Autodesk Fusion 360 part; units mm, degrees
(part 7 of 7)
equation "d574 = abs(mountInset - 10 mm)"
equation "d576 = 2 * panelHeight - 2 * mountInset + 20 mm"
equation "d579 = frameZ"
equation "d581 = abs(2 * panelWidth - mountInset - 10 mm)"
equation "d582 = abs(mountInset - 10 mm)"
equation "d584 = 2 * panelHeight - 2 * mountInset + 20 mm"
equation "d587 = frameZ"
equation "d589 = abs(2 * panelWidth - mountInset - 10 mm + 7 mm)"
equation "d590 = abs(mountInset - 10 mm)"
equation "d592 = 2 * panelHeight - 2 * mountInset + 20 mm"
equation "d595 = frameZ + 1.8 mm"
equation "d597 = abs(2 * panelWidth - mountInset - 10 mm + 5 mm)"
equation "d598 = abs(mountInset - 10 mm)"
equation "d600 = 2 * panelHeight - 2 * mountInset + 20 mm"
equation "d603 = frameZ"
equation "d605 = abs(mountInset + 10 mm)"
equation "d606 = abs(mountInset - 10 mm)"
equation "d607 = panelWidth - ( mountInset ) - 20 mm"
equation "d611 = frameZ"
equation "d613 = abs(mountInset + 10 mm)"
equation "d614 = abs(mountInset - 10 mm + 7 mm)"
equation "d615 = panelWidth - ( mountInset ) - 20 mm"
equation "d619 = frameZ + 1.8 mm"
equation "d621 = abs(mountInset + 10 mm)"
equation "d622 = abs(mountInset - 10 mm + 5 mm)"
equation "d623 = panelWidth - ( mountInset ) - 20 mm"
equation "d627 = frameZ"
equation "d629 = abs(panelWidth + 10 mm)"
equation "d630 = abs(mountInset - 10 mm)"
equation "d631 = 2 * panelWidth - mountInset - ( panelWidth ) - 20 mm"
equation "d635 = frameZ"
equation "d637 = abs(panelWidth + 10 mm)"
equation "d638 = abs(mountInset - 10 mm + 7 mm)"
equation "d639 = 2 * panelWidth - mountInset - ( panelWidth ) - 20 mm"
equation "d643 = frameZ + 1.8 mm"
equation "d645 = abs(panelWidth + 10 mm)"
equation "d646 = abs(mountInset - 10 mm + 5 mm)"
equation "d647 = 2 * panelWidth - mountInset - ( panelWidth ) - 20 mm"
equation "d651 = frameZ"
equation "d653 = abs(mountInset + 10 mm)"
equation "d654 = abs(2 * panelHeight - mountInset - 10 mm)"
equation "d655 = panelWidth - ( mountInset ) - 20 mm"
equation "d659 = frameZ"
equation "d661 = abs(mountInset + 10 mm)"
equation "d662 = abs(2 * panelHeight - mountInset - 10 mm + 7 mm)"
equation "d663 = panelWidth - ( mountInset ) - 20 mm"
equation "d667 = frameZ + 1.8 mm"
equation "d669 = abs(mountInset + 10 mm)"
equation "d670 = abs(2 * panelHeight - mountInset - 10 mm + 5 mm)"
equation "d671 = panelWidth - ( mountInset ) - 20 mm"
equation "d675 = frameZ"
equation "d677 = abs(panelWidth + 10 mm)"
equation "d678 = abs(2 * panelHeight - mountInset - 10 mm)"
equation "d679 = 2 * panelWidth - mountInset - ( panelWidth ) - 20 mm"
equation "d683 = frameZ"
equation "d685 = abs(panelWidth + 10 mm)"
equation "d686 = abs(2 * panelHeight - mountInset - 10 mm + 7 mm)"
equation "d687 = 2 * panelWidth - mountInset - ( panelWidth ) - 20 mm"
equation "d691 = frameZ + 1.8 mm"
equation "d693 = abs(panelWidth + 10 mm)"
equation "d694 = abs(2 * panelHeight - mountInset - 10 mm + 5 mm)"
equation "d695 = 2 * panelWidth - mountInset - ( panelWidth ) - 20 mm"
equation "d699 = -capThickness"
equation "d701 = abs(mountInset)"
equation "d702 = abs(mountInset)"
equation "d703 = capDiameter"
equation "d704 = capThickness"
equation "d706 = -capThickness"
equation "d708 = abs(mountInset)"
equation "d709 = abs(mountInset)"
equation "d710 = screwClearance"
equation "d711 = capThickness"
equation "d713 = boardThickness"
equation "d715 = abs(mountInset)"
equation "d716 = abs(mountInset)"
equation "d717 = capDiameter"
equation "d718 = seatThickness"
equation "d720 = boardThickness"
equation "d722 = abs(mountInset)"
equation "d723 = abs(mountInset)"
equation "d724 = mountBore"
equation "d725 = seatThickness"
equation "d727 = abs(mountInset)"
equation "d728 = abs(mountInset)"
equation "d730 = boardThickness + seatThickness"
equation "d732 = boardThickness + seatThickness"
equation "d734 = abs(mountInset)"
equation "d735 = abs(mountInset)"
equation "d737 = hookClearance - seatThickness"
equation "d739 = abs(mountInset)"
equation "d740 = abs(mountInset)"
equation "d741 = screwClearance"
equation "d742 = frameZ"
equation "d744 = -capThickness - 3 mm"
equation "d746 = abs(mountInset)"
equation "d747 = abs(mountInset)"
equation "d751 = -capThickness"
equation "d753 = abs(mountInset)"
equation "d754 = abs(mountInset)"
equation "d755 = screwDiameter"
equation "d756 = frameZ + capThickness + 5 mm"
equation "d758 = frameZ + 2 mm"
equation "d760 = abs(mountInset - 4.8 mm)"
equation "d761 = abs(mountInset - 5 mm)"
equation "d766 = frameZ + 2 mm"
equation "d768 = abs(mountInset)"
equation "d769 = abs(mountInset)"
equation "d775 = -capThickness"
equation "d777 = abs(mountInset)"
equation "d778 = abs(panelHeight)"
equation "d779 = capDiameter"
equation "d780 = capThickness"
equation "d782 = -capThickness"
equation "d784 = abs(mountInset)"
equation "d785 = abs(panelHeight)"
equation "d786 = screwClearance"
equation "d787 = capThickness"
equation "d789 = boardThickness"
equation "d791 = abs(mountInset)"
equation "d792 = abs(panelHeight)"
equation "d793 = capDiameter"
equation "d794 = seatThickness"
equation "d796 = boardThickness"
equation "d798 = abs(mountInset)"
equation "d799 = abs(panelHeight)"
equation "d800 = mountBore"
equation "d801 = seatThickness"
equation "d803 = abs(mountInset)"
equation "d804 = abs(panelHeight)"
equation "d806 = boardThickness + seatThickness"
equation "d808 = boardThickness + seatThickness"
equation "d810 = abs(mountInset)"
equation "d811 = abs(panelHeight)"
equation "d813 = hookClearance - seatThickness"
equation "d815 = abs(mountInset)"
equation "d816 = abs(panelHeight)"
equation "d817 = screwClearance"
equation "d818 = frameZ"
equation "d820 = -capThickness - 3 mm"
equation "d822 = abs(mountInset)"
equation "d823 = abs(panelHeight)"
equation "d827 = -capThickness"
equation "d829 = abs(mountInset)"
equation "d830 = abs(panelHeight)"
equation "d831 = screwDiameter"
equation "d832 = frameZ + capThickness + 5 mm"
equation "d834 = frameZ + 2 mm"
equation "d836 = abs(mountInset - 4.8 mm)"
equation "d837 = abs(panelHeight - 5 mm)"
equation "d842 = frameZ + 2 mm"
equation "d844 = abs(mountInset)"
equation "d845 = abs(panelHeight)"
equation "d851 = -capThickness"
equation "d853 = abs(mountInset)"
equation "d854 = abs(2 * panelHeight - mountInset)"
equation "d855 = capDiameter"
equation "d856 = capThickness"
equation "d858 = -capThickness"
equation "d860 = abs(mountInset)"
equation "d861 = abs(2 * panelHeight - mountInset)"
equation "d862 = screwClearance"
equation "d863 = capThickness"
equation "d865 = boardThickness"
equation "d867 = abs(mountInset)"
equation "d868 = abs(2 * panelHeight - mountInset)"
equation "d869 = capDiameter"
equation "d870 = seatThickness"
equation "d872 = boardThickness"
equation "d874 = abs(mountInset)"
equation "d875 = abs(2 * panelHeight - mountInset)"
equation "d876 = mountBore"
equation "d877 = seatThickness"
equation "d879 = abs(mountInset)"
equation "d880 = abs(2 * panelHeight - mountInset)"
equation "d882 = boardThickness + seatThickness"
equation "d884 = boardThickness + seatThickness"
equation "d886 = abs(mountInset)"
equation "d887 = abs(2 * panelHeight - mountInset)"
equation "d889 = hookClearance - seatThickness"
equation "d891 = abs(mountInset)"
equation "d892 = abs(2 * panelHeight - mountInset)"
equation "d893 = screwClearance"
equation "d894 = frameZ"
equation "d896 = -capThickness - 3 mm"
equation "d898 = abs(mountInset)"
equation "d899 = abs(2 * panelHeight - mountInset)"
equation "d903 = -capThickness"
equation "d905 = abs(mountInset)"
equation "d906 = abs(2 * panelHeight - mountInset)"
equation "d907 = screwDiameter"
equation "d908 = frameZ + capThickness + 5 mm"
equation "d910 = frameZ + 2 mm"
equation "d912 = abs(mountInset - 4.8 mm)"
equation "d913 = abs(2 * panelHeight - mountInset - 5 mm)"
equation "d918 = frameZ + 2 mm"
equation "d920 = abs(mountInset)"
equation "d921 = abs(2 * panelHeight - mountInset)"
equation "d927 = -capThickness"
equation "d929 = abs(panelWidth)"
equation "d930 = abs(mountInset)"
equation "d931 = capDiameter"
equation "d932 = capThickness"
equation "d934 = -capThickness"
equation "d936 = abs(panelWidth)"
equation "d937 = abs(mountInset)"
equation "d938 = screwClearance"
equation "d939 = capThickness"
equation "d941 = boardThickness"
equation "d943 = abs(panelWidth)"
equation "d944 = abs(mountInset)"
equation "d945 = capDiameter"
equation "d946 = seatThickness"
equation "d948 = boardThickness"
equation "d950 = abs(panelWidth)"
equation "d951 = abs(mountInset)"
equation "d952 = mountBore"
equation "d953 = seatThickness"
equation "d955 = abs(panelWidth)"
equation "d956 = abs(mountInset)"
equation "d958 = boardThickness + seatThickness"
equation "d960 = boardThickness + seatThickness"
equation "d962 = abs(panelWidth)"
equation "d963 = abs(mountInset)"
equation "d965 = hookClearance - seatThickness"
equation "d967 = abs(panelWidth)"
equation "d968 = abs(mountInset)"
equation "d969 = screwClearance"
equation "d970 = frameZ"
equation "d972 = -capThickness - 3 mm"
equation "d974 = abs(panelWidth)"
equation "d975 = abs(mountInset)"
equation "d979 = -capThickness"
equation "d981 = abs(panelWidth)"
equation "d982 = abs(mountInset)"
equation "d983 = screwDiameter"
equation "d984 = frameZ + capThickness + 5 mm"
equation "d986 = frameZ + 2 mm"
equation "d988 = abs(panelWidth - 4.8 mm)"
equation "d989 = abs(mountInset - 5 mm)"
equation "d994 = frameZ + 2 mm"
equation "d996 = abs(panelWidth)"
equation "d997 = abs(mountInset)"
equation "d1003 = -capThickness"
equation "d1005 = abs(panelWidth)"
equation "d1006 = abs(panelHeight)"
equation "d1007 = capDiameter"
equation "d1008 = capThickness"
equation "d1010 = -capThickness"
equation "d1012 = abs(panelWidth)"
equation "d1013 = abs(panelHeight)"
equation "d1014 = screwClearance"
equation "d1015 = capThickness"
equation "d1017 = boardThickness"
equation "d1019 = abs(panelWidth)"
equation "d1020 = abs(panelHeight)"
equation "d1021 = capDiameter"
equation "d1022 = seatThickness"
equation "d1024 = boardThickness"
equation "d1026 = abs(panelWidth)"
equation "d1027 = abs(panelHeight)"
equation "d1028 = mountBore"
equation "d1029 = seatThickness"
equation "d1031 = abs(panelWidth)"
equation "d1032 = abs(panelHeight)"
equation "d1034 = boardThickness + seatThickness"
equation "d1036 = boardThickness + seatThickness"
equation "d1038 = abs(panelWidth)"
equation "d1039 = abs(panelHeight)"
equation "d1041 = hookClearance - seatThickness"
equation "d1043 = abs(panelWidth)"
equation "d1044 = abs(panelHeight)"
equation "d1045 = screwClearance"
equation "d1046 = frameZ"
equation "d1048 = -capThickness - 3 mm"
equation "d1050 = abs(panelWidth)"
equation "d1051 = abs(panelHeight)"
equation "d1055 = -capThickness"
equation "d1057 = abs(panelWidth)"
equation "d1058 = abs(panelHeight)"
equation "d1059 = screwDiameter"
equation "d1060 = frameZ + capThickness + 5 mm"
equation "d1062 = frameZ + 2 mm"
equation "d1064 = abs(panelWidth - 4.8 mm)"
equation "d1065 = abs(panelHeight - 5 mm)"
equation "d1070 = frameZ + 2 mm"
equation "d1072 = abs(panelWidth)"
equation "d1073 = abs(panelHeight)"
equation "d1079 = -capThickness"
equation "d1081 = abs(panelWidth)"
equation "d1082 = abs(2 * panelHeight - mountInset)"
equation "d1083 = capDiameter"
equation "d1084 = capThickness"
equation "d1086 = -capThickness"
equation "d1088 = abs(panelWidth)"
equation "d1089 = abs(2 * panelHeight - mountInset)"
equation "d1090 = screwClearance"
equation "d1091 = capThickness"
equation "d1093 = boardThickness"
equation "d1095 = abs(panelWidth)"
equation "d1096 = abs(2 * panelHeight - mountInset)"
equation "d1097 = capDiameter"
equation "d1098 = seatThickness"
equation "d1100 = boardThickness"
equation "d1102 = abs(panelWidth)"
equation "d1103 = abs(2 * panelHeight - mountInset)"
equation "d1104 = mountBore"
equation "d1105 = seatThickness"
equation "d1107 = abs(panelWidth)"
equation "d1108 = abs(2 * panelHeight - mountInset)"
equation "d1110 = boardThickness + seatThickness"
equation "d1112 = boardThickness + seatThickness"
equation "d1114 = abs(panelWidth)"
equation "d1115 = abs(2 * panelHeight - mountInset)"
equation "d1117 = hookClearance - seatThickness"
equation "d1119 = abs(panelWidth)"
equation "d1120 = abs(2 * panelHeight - mountInset)"
equation "d1121 = screwClearance"
equation "d1122 = frameZ"
equation "d1124 = -capThickness - 3 mm"
equation "d1126 = abs(panelWidth)"
equation "d1127 = abs(2 * panelHeight - mountInset)"
equation "d1131 = -capThickness"
equation "d1133 = abs(panelWidth)"
equation "d1134 = abs(2 * panelHeight - mountInset)"
equation "d1135 = screwDiameter"
equation "d1136 = frameZ + capThickness + 5 mm"
equation "d1138 = frameZ + 2 mm"
equation "d1140 = abs(panelWidth - 4.8 mm)"
equation "d1141 = abs(2 * panelHeight - mountInset - 5 mm)"
equation "d1146 = frameZ + 2 mm"
equation "d1148 = abs(panelWidth)"
equation "d1149 = abs(2 * panelHeight - mountInset)"
equation "d1155 = -capThickness"
equation "d1157 = abs(2 * panelWidth - mountInset)"
equation "d1158 = abs(mountInset)"
equation "d1159 = capDiameter"
equation "d1160 = capThickness"
equation "d1162 = -capThickness"
equation "d1164 = abs(2 * panelWidth - mountInset)"
equation "d1165 = abs(mountInset)"
equation "d1166 = screwClearance"
equation "d1167 = capThickness"
equation "d1169 = boardThickness"
equation "d1171 = abs(2 * panelWidth - mountInset)"
equation "d1172 = abs(mountInset)"
equation "d1173 = capDiameter"
equation "d1174 = seatThickness"
equation "d1176 = boardThickness"
equation "d1178 = abs(2 * panelWidth - mountInset)"
equation "d1179 = abs(mountInset)"
equation "d1180 = mountBore"
equation "d1181 = seatThickness"
equation "d1183 = abs(2 * panelWidth - mountInset)"
equation "d1184 = abs(mountInset)"
equation "d1186 = boardThickness + seatThickness"
equation "d1188 = boardThickness + seatThickness"
equation "d1190 = abs(2 * panelWidth - mountInset)"
equation "d1191 = abs(mountInset)"
equation "d1193 = hookClearance - seatThickness"
equation "d1195 = abs(2 * panelWidth - mountInset)"
equation "d1196 = abs(mountInset)"
equation "d1197 = screwClearance"
equation "d1198 = frameZ"
equation "d1200 = -capThickness - 3 mm"
equation "d1202 = abs(2 * panelWidth - mountInset)"
equation "d1203 = abs(mountInset)"
equation "d1207 = -capThickness"
equation "d1209 = abs(2 * panelWidth - mountInset)"
equation "d1210 = abs(mountInset)"
equation "d1211 = screwDiameter"
equation "d1212 = frameZ + capThickness + 5 mm"
equation "d1214 = frameZ + 2 mm"
equation "d1216 = abs(2 * panelWidth - mountInset - 4.8 mm)"
equation "d1217 = abs(mountInset - 5 mm)"
equation "d1222 = frameZ + 2 mm"
equation "d1224 = abs(2 * panelWidth - mountInset)"
equation "d1225 = abs(mountInset)"
equation "d1231 = -capThickness"
equation "d1233 = abs(2 * panelWidth - mountInset)"
equation "d1234 = abs(panelHeight)"
equation "d1235 = capDiameter"
equation "d1236 = capThickness"
equation "d1238 = -capThickness"
equation "d1240 = abs(2 * panelWidth - mountInset)"
equation "d1241 = abs(panelHeight)"
equation "d1242 = screwClearance"
equation "d1243 = capThickness"
equation "d1245 = boardThickness"
equation "d1247 = abs(2 * panelWidth - mountInset)"
equation "d1248 = abs(panelHeight)"
equation "d1249 = capDiameter"
equation "d1250 = seatThickness"
equation "d1252 = boardThickness"
equation "d1254 = abs(2 * panelWidth - mountInset)"
equation "d1255 = abs(panelHeight)"
equation "d1256 = mountBore"
equation "d1257 = seatThickness"
equation "d1259 = abs(2 * panelWidth - mountInset)"
equation "d1260 = abs(panelHeight)"
equation "d1262 = boardThickness + seatThickness"
equation "d1264 = boardThickness + seatThickness"
equation "d1266 = abs(2 * panelWidth - mountInset)"
equation "d1267 = abs(panelHeight)"
equation "d1269 = hookClearance - seatThickness"
equation "d1271 = abs(2 * panelWidth - mountInset)"
equation "d1272 = abs(panelHeight)"
equation "d1273 = screwClearance"
equation "d1274 = frameZ"
equation "d1276 = -capThickness - 3 mm"
equation "d1278 = abs(2 * panelWidth - mountInset)"
equation "d1279 = abs(panelHeight)"
equation "d1283 = -capThickness"
equation "d1285 = abs(2 * panelWidth - mountInset)"
equation "d1286 = abs(panelHeight)"
equation "d1287 = screwDiameter"
equation "d1288 = frameZ + capThickness + 5 mm"
equation "d1290 = frameZ + 2 mm"
equation "d1292 = abs(2 * panelWidth - mountInset - 4.8 mm)"
equation "d1293 = abs(panelHeight - 5 mm)"
equation "d1298 = frameZ + 2 mm"
equation "d1300 = abs(2 * panelWidth - mountInset)"
equation "d1301 = abs(panelHeight)"
equation "d1307 = -capThickness"
equation "d1309 = abs(2 * panelWidth - mountInset)"
equation "d1310 = abs(2 * panelHeight - mountInset)"
equation "d1311 = capDiameter"
equation "d1312 = capThickness"
equation "d1314 = -capThickness"
equation "d1316 = abs(2 * panelWidth - mountInset)"
equation "d1317 = abs(2 * panelHeight - mountInset)"
equation "d1318 = screwClearance"
equation "d1319 = capThickness"
equation "d1321 = boardThickness"
equation "d1323 = abs(2 * panelWidth - mountInset)"
equation "d1324 = abs(2 * panelHeight - mountInset)"
equation "d1325 = capDiameter"
equation "d1326 = seatThickness"
equation "d1328 = boardThickness"
equation "d1330 = abs(2 * panelWidth - mountInset)"
equation "d1331 = abs(2 * panelHeight - mountInset)"
equation "d1332 = mountBore"
equation "d1333 = seatThickness"
equation "d1335 = abs(2 * panelWidth - mountInset)"
equation "d1336 = abs(2 * panelHeight - mountInset)"
equation "d1338 = boardThickness + seatThickness"
equation "d1340 = boardThickness + seatThickness"
equation "d1342 = abs(2 * panelWidth - mountInset)"
equation "d1343 = abs(2 * panelHeight - mountInset)"
equation "d1345 = hookClearance - seatThickness"
equation "d1347 = abs(2 * panelWidth - mountInset)"
equation "d1348 = abs(2 * panelHeight - mountInset)"
equation "d1349 = screwClearance"
equation "d1350 = frameZ"
equation "d1352 = -capThickness - 3 mm"
equation "d1354 = abs(2 * panelWidth - mountInset)"
equation "d1355 = abs(2 * panelHeight - mountInset)"
equation "d1359 = -capThickness"
equation "d1361 = abs(2 * panelWidth - mountInset)"
equation "d1362 = abs(2 * panelHeight - mountInset)"
equation "d1363 = screwDiameter"
equation "d1364 = frameZ + capThickness + 5 mm"
equation "d1366 = frameZ + 2 mm"
equation "d1368 = abs(2 * panelWidth - mountInset - 4.8 mm)"
equation "d1369 = abs(2 * panelHeight - mountInset - 5 mm)"
equation "d1374 = frameZ + 2 mm"
equation "d1376 = abs(2 * panelWidth - mountInset)"
equation "d1377 = abs(2 * panelHeight - mountInset)"
equation "d1383 = frameZ + 20 mm"
equation "d1385 = abs(mountInset - 3 mm)"
equation "d1386 = abs(mountInset - 10 mm)"
equation "d1388 = 2 * panelHeight - 2 * mountInset + 20 mm"
equation "d1391 = frameZ + 18.2 mm"
equation "d1393 = abs(mountInset - 5 mm)"
equation "d1394 = abs(mountInset - 10 mm)"
equation "d1396 = 2 * panelHeight - 2 * mountInset + 20 mm"
equation "d1399 = frameZ + 20 mm"
equation "d1401 = abs(panelWidth - 3 mm)"
equation "d1402 = abs(mountInset - 10 mm)"
equation "d1404 = 2 * panelHeight - 2 * mountInset + 20 mm"
equation "d1407 = frameZ + 18.2 mm"
equation "d1409 = abs(panelWidth - 5 mm)"
equation "d1410 = abs(mountInset - 10 mm)"
equation "d1412 = 2 * panelHeight - 2 * mountInset + 20 mm"
equation "d1415 = frameZ + 20 mm"
equation "d1417 = abs(2 * panelWidth - mountInset - 3 mm)"
equation "d1418 = abs(mountInset - 10 mm)"
equation "d1420 = 2 * panelHeight - 2 * mountInset + 20 mm"
equation "d1423 = frameZ + 18.2 mm"
equation "d1425 = abs(2 * panelWidth - mountInset - 5 mm)"
equation "d1426 = abs(mountInset - 10 mm)"
equation "d1428 = 2 * panelHeight - 2 * mountInset + 20 mm"
equation "d1431 = frameZ + 20 mm"
equation "d1433 = abs(mountInset + 10 mm)"
equation "d1434 = abs(mountInset - 3 mm)"
equation "d1435 = panelWidth - ( mountInset ) - 20 mm"
equation "d1439 = frameZ + 18.2 mm"
equation "d1441 = abs(mountInset + 10 mm)"
equation "d1442 = abs(mountInset - 5 mm)"
equation "d1443 = panelWidth - ( mountInset ) - 20 mm"
equation "d1447 = frameZ + 20 mm"
equation "d1449 = abs(panelWidth + 10 mm)"
equation "d1450 = abs(mountInset - 3 mm)"
equation "d1451 = 2 * panelWidth - mountInset - ( panelWidth ) - 20 mm"
equation "d1455 = frameZ + 18.2 mm"
equation "d1457 = abs(panelWidth + 10 mm)"
equation "d1458 = abs(mountInset - 5 mm)"
equation "d1459 = 2 * panelWidth - mountInset - ( panelWidth ) - 20 mm"
equation "d1463 = frameZ + 20 mm"
equation "d1465 = abs(mountInset + ( -8 mm ))"
equation "d1466 = abs(mountInset - 8 mm)"
equation "d1471 = frameZ + 20 mm"
equation "d1473 = abs(mountInset + ( 0 mm ))"
equation "d1474 = abs(mountInset)"
equation "d1478 = frameZ + 23 mm"
equation "d1480 = abs(mountInset + ( 0 mm ))"
equation "d1481 = abs(mountInset)"
equation "d1485 = frameZ + 23 mm"
equation "d1487 = abs(mountInset + ( 0 mm ))"
equation "d1488 = abs(mountInset)"
equation "d1492 = frameZ + 14 mm"
equation "d1494 = abs(mountInset + ( 0 mm ) - 4.8 mm)"
equation "d1495 = abs(mountInset - 4.8 mm)"
equation "d1500 = frameZ + 14 mm"
equation "d1502 = abs(mountInset + ( 0 mm ))"
equation "d1503 = abs(mountInset)"
equation "d1509 = frameZ + 20 mm"
equation "d1511 = abs(mountInset + ( 20 mm ))"
equation "d1512 = abs(mountInset)"
equation "d1516 = frameZ + 23 mm"
equation "d1518 = abs(mountInset + ( 20 mm ))"
equation "d1519 = abs(mountInset)"
equation "d1523 = frameZ + 23 mm"
equation "d1525 = abs(mountInset + ( 20 mm ))"
equation "d1526 = abs(mountInset)"
equation "d1530 = frameZ + 14 mm"
equation "d1532 = abs(mountInset + ( 20 mm ) - 4.8 mm)"
equation "d1533 = abs(mountInset - 4.8 mm)"
equation "d1538 = frameZ + 14 mm"
equation "d1540 = abs(mountInset + ( 20 mm ))"
equation "d1541 = abs(mountInset)"
equation "d1547 = frameZ + 20 mm"
equation "d1549 = abs(panelWidth + ( -28 mm ))"
equation "d1550 = abs(mountInset - 8 mm)"
equation "d1555 = frameZ + 20 mm"
equation "d1557 = abs(panelWidth + ( -20 mm ))"
equation "d1558 = abs(mountInset)"
equation "d1562 = frameZ + 23 mm"
equation "d1564 = abs(panelWidth + ( -20 mm ))"
equation "d1565 = abs(mountInset)"
equation "d1569 = frameZ + 23 mm"
equation "d1571 = abs(panelWidth + ( -20 mm ))"
equation "d1572 = abs(mountInset)"
equation "d1576 = frameZ + 14 mm"
equation "d1578 = abs(panelWidth + ( -20 mm ) - 4.8 mm)"
equation "d1579 = abs(mountInset - 4.8 mm)"
equation "d1584 = frameZ + 14 mm"
equation "d1586 = abs(panelWidth + ( -20 mm ))"
equation "d1587 = abs(mountInset)"
equation "d1593 = frameZ + 20 mm"
equation "d1595 = abs(panelWidth + ( 0 mm ))"
equation "d1596 = abs(mountInset)"
equation "d1600 = frameZ + 23 mm"
equation "d1602 = abs(panelWidth + ( 0 mm ))"
equation "d1603 = abs(mountInset)"
equation "d1607 = frameZ + 23 mm"
equation "d1609 = abs(panelWidth + ( 0 mm ))"
equation "d1610 = abs(mountInset)"
equation "d1614 = frameZ + 14 mm"
equation "d1616 = abs(panelWidth + ( 0 mm ) - 4.8 mm)"
equation "d1617 = abs(mountInset - 4.8 mm)"
equation "d1622 = frameZ + 14 mm"
equation "d1624 = abs(panelWidth + ( 0 mm ))"
equation "d1625 = abs(mountInset)"
equation "d1631 = frameZ + 20 mm"
equation "d1633 = abs(panelWidth + ( 20 mm ))"
equation "d1634 = abs(mountInset)"
equation "d1638 = frameZ + 23 mm"
equation "d1640 = abs(panelWidth + ( 20 mm ))"
equation "d1641 = abs(mountInset)"
equation "d1645 = frameZ + 23 mm"
equation "d1647 = abs(panelWidth + ( 20 mm ))"
equation "d1648 = abs(mountInset)"
equation "d1652 = frameZ + 14 mm"
equation "d1654 = abs(panelWidth + ( 20 mm ) - 4.8 mm)"
equation "d1655 = abs(mountInset - 4.8 mm)"
equation "d1660 = frameZ + 14 mm"
equation "d1662 = abs(panelWidth + ( 20 mm ))"
equation "d1663 = abs(mountInset)"
equation "d1669 = frameZ + 20 mm"
equation "d1671 = abs(2 * panelWidth - mountInset + ( -28 mm ))"
equation "d1672 = abs(mountInset - 8 mm)"
equation "d1677 = frameZ + 20 mm"
equation "d1679 = abs(2 * panelWidth - mountInset + ( -20 mm ))"
equation "d1680 = abs(mountInset)"
equation "d1684 = frameZ + 23 mm"
equation "d1686 = abs(2 * panelWidth - mountInset + ( -20 mm ))"
equation "d1687 = abs(mountInset)"
equation "d1691 = frameZ + 23 mm"
equation "d1693 = abs(2 * panelWidth - mountInset + ( -20 mm ))"
equation "d1694 = abs(mountInset)"
equation "d1698 = frameZ + 14 mm"
equation "d1700 = abs(2 * panelWidth - mountInset + ( -20 mm ) - 4.8 mm)"
equation "d1701 = abs(mountInset - 4.8 mm)"
equation "d1706 = frameZ + 14 mm"
equation "d1708 = abs(2 * panelWidth - mountInset + ( -20 mm ))"
equation "d1709 = abs(mountInset)"
equation "d1715 = frameZ + 20 mm"
equation "d1717 = abs(2 * panelWidth - mountInset + ( 0 mm ))"
equation "d1718 = abs(mountInset)"
equation "d1722 = frameZ + 23 mm"
equation "d1724 = abs(2 * panelWidth - mountInset + ( 0 mm ))"
equation "d1725 = abs(mountInset)"
equation "d1729 = frameZ + 23 mm"
equation "d1731 = abs(2 * panelWidth - mountInset + ( 0 mm ))"
equation "d1732 = abs(mountInset)"
equation "d1736 = frameZ + 14 mm"
equation "d1738 = abs(2 * panelWidth - mountInset + ( 0 mm ) - 4.8 mm)"
equation "d1739 = abs(mountInset - 4.8 mm)"
equation "d1744 = frameZ + 14 mm"
equation "d1746 = abs(2 * panelWidth - mountInset + ( 0 mm ))"
equation "d1747 = abs(mountInset)"
equation "d1753 = frameZ + 20 mm"
equation "d1755 = abs(mountInset + 10 mm)"
equation "d1756 = abs(2 * panelHeight - mountInset - 3 mm)"
equation "d1757 = panelWidth - ( mountInset ) - 20 mm"
equation "d1761 = frameZ + 18.2 mm"
equation "d1763 = abs(mountInset + 10 mm)"
equation "d1764 = abs(2 * panelHeight - mountInset - 5 mm)"
equation "d1765 = panelWidth - ( mountInset ) - 20 mm"
equation "d1769 = frameZ + 20 mm"
equation "d1771 = abs(panelWidth + 10 mm)"
equation "d1772 = abs(2 * panelHeight - mountInset - 3 mm)"
equation "d1773 = 2 * panelWidth - mountInset - ( panelWidth ) - 20 mm"
equation "d1777 = frameZ + 18.2 mm"
equation "d1779 = abs(panelWidth + 10 mm)"
equation "d1780 = abs(2 * panelHeight - mountInset - 5 mm)"
equation "d1781 = 2 * panelWidth - mountInset - ( panelWidth ) - 20 mm"
equation "d1785 = frameZ + 20 mm"
equation "d1787 = abs(mountInset + ( -8 mm ))"
equation "d1788 = abs(2 * panelHeight - mountInset - 8 mm)"
equation "d1793 = frameZ + 20 mm"
equation "d1795 = abs(mountInset + ( 0 mm ))"
equation "d1796 = abs(2 * panelHeight - mountInset)"
equation "d1800 = frameZ + 23 mm"
equation "d1802 = abs(mountInset + ( 0 mm ))"
equation "d1803 = abs(2 * panelHeight - mountInset)"
equation "d1807 = frameZ + 23 mm"
equation "d1809 = abs(mountInset + ( 0 mm ))"
equation "d1810 = abs(2 * panelHeight - mountInset)"
equation "d1814 = frameZ + 14 mm"
equation "d1816 = abs(mountInset + ( 0 mm ) - 4.8 mm)"
equation "d1817 = abs(2 * panelHeight - mountInset - 4.8 mm)"
equation "d1822 = frameZ + 14 mm"
equation "d1824 = abs(mountInset + ( 0 mm ))"
equation "d1825 = abs(2 * panelHeight - mountInset)"
equation "d1831 = frameZ + 20 mm"
equation "d1833 = abs(mountInset + ( 20 mm ))"
equation "d1834 = abs(2 * panelHeight - mountInset)"
equation "d1838 = frameZ + 23 mm"
equation "d1840 = abs(mountInset + ( 20 mm ))"
equation "d1841 = abs(2 * panelHeight - mountInset)"
equation "d1845 = frameZ + 23 mm"
equation "d1847 = abs(mountInset + ( 20 mm ))"
equation "d1848 = abs(2 * panelHeight - mountInset)"
equation "d1852 = frameZ + 14 mm"
equation "d1854 = abs(mountInset + ( 20 mm ) - 4.8 mm)"
equation "d1855 = abs(2 * panelHeight - mountInset - 4.8 mm)"
equation "d1860 = frameZ + 14 mm"
equation "d1862 = abs(mountInset + ( 20 mm ))"
equation "d1863 = abs(2 * panelHeight - mountInset)"
equation "d1869 = frameZ + 20 mm"
equation "d1871 = abs(panelWidth + ( -28 mm ))"
equation "d1872 = abs(2 * panelHeight - mountInset - 8 mm)"
equation "d1877 = frameZ + 20 mm"
equation "d1879 = abs(panelWidth + ( -20 mm ))"
equation "d1880 = abs(2 * panelHeight - mountInset)"
equation "d1884 = frameZ + 23 mm"
equation "d1886 = abs(panelWidth + ( -20 mm ))"
equation "d1887 = abs(2 * panelHeight - mountInset)"
equation "d1891 = frameZ + 23 mm"
equation "d1893 = abs(panelWidth + ( -20 mm ))"
equation "d1894 = abs(2 * panelHeight - mountInset)"
equation "d1898 = frameZ + 14 mm"
equation "d1900 = abs(panelWidth + ( -20 mm ) - 4.8 mm)"
equation "d1901 = abs(2 * panelHeight - mountInset - 4.8 mm)"
equation "d1906 = frameZ + 14 mm"
equation "d1908 = abs(panelWidth + ( -20 mm ))"
equation "d1909 = abs(2 * panelHeight - mountInset)"
equation "d1915 = frameZ + 20 mm"
equation "d1917 = abs(panelWidth + ( 0 mm ))"
equation "d1918 = abs(2 * panelHeight - mountInset)"
equation "d1922 = frameZ + 23 mm"
equation "d1924 = abs(panelWidth + ( 0 mm ))"
equation "d1925 = abs(2 * panelHeight - mountInset)"
equation "d1929 = frameZ + 23 mm"
equation "d1931 = abs(panelWidth + ( 0 mm ))"
equation "d1932 = abs(2 * panelHeight - mountInset)"
equation "d1936 = frameZ + 14 mm"
equation "d1938 = abs(panelWidth + ( 0 mm ) - 4.8 mm)"
equation "d1939 = abs(2 * panelHeight - mountInset - 4.8 mm)"
equation "d1944 = frameZ + 14 mm"
equation "d1946 = abs(panelWidth + ( 0 mm ))"
equation "d1947 = abs(2 * panelHeight - mountInset)"
equation "d1953 = frameZ + 20 mm"
equation "d1955 = abs(panelWidth + ( 20 mm ))"
equation "d1956 = abs(2 * panelHeight - mountInset)"
equation "d1960 = frameZ + 23 mm"
equation "d1962 = abs(panelWidth + ( 20 mm ))"
equation "d1963 = abs(2 * panelHeight - mountInset)"
equation "d1967 = frameZ + 23 mm"
equation "d1969 = abs(panelWidth + ( 20 mm ))"
equation "d1970 = abs(2 * panelHeight - mountInset)"
equation "d1974 = frameZ + 14 mm"
equation "d1976 = abs(panelWidth + ( 20 mm ) - 4.8 mm)"
equation "d1977 = abs(2 * panelHeight - mountInset - 4.8 mm)"
equation "d1982 = frameZ + 14 mm"
equation "d1984 = abs(panelWidth + ( 20 mm ))"
equation "d1985 = abs(2 * panelHeight - mountInset)"
equation "d1991 = frameZ + 20 mm"
equation "d1993 = abs(2 * panelWidth - mountInset + ( -28 mm ))"
equation "d1994 = abs(2 * panelHeight - mountInset - 8 mm)"
equation "d1999 = frameZ + 20 mm"
equation "d2001 = abs(2 * panelWidth - mountInset + ( -20 mm ))"
equation "d2002 = abs(2 * panelHeight - mountInset)"
equation "d2006 = frameZ + 23 mm"
equation "d2008 = abs(2 * panelWidth - mountInset + ( -20 mm ))"
equation "d2009 = abs(2 * panelHeight - mountInset)"
equation "d2013 = frameZ + 23 mm"
equation "d2015 = abs(2 * panelWidth - mountInset + ( -20 mm ))"
equation "d2016 = abs(2 * panelHeight - mountInset)"
equation "d2020 = frameZ + 14 mm"
equation "d2022 = abs(2 * panelWidth - mountInset + ( -20 mm ) - 4.8 mm)"
equation "d2023 = abs(2 * panelHeight - mountInset - 4.8 mm)"
equation "d2028 = frameZ + 14 mm"
equation "d2030 = abs(2 * panelWidth - mountInset + ( -20 mm ))"
equation "d2031 = abs(2 * panelHeight - mountInset)"
equation "d2037 = frameZ + 20 mm"
equation "d2039 = abs(2 * panelWidth - mountInset + ( 0 mm ))"
equation "d2040 = abs(2 * panelHeight - mountInset)"
equation "d2044 = frameZ + 23 mm"
equation "d2046 = abs(2 * panelWidth - mountInset + ( 0 mm ))"
equation "d2047 = abs(2 * panelHeight - mountInset)"
equation "d2051 = frameZ + 23 mm"
equation "d2053 = abs(2 * panelWidth - mountInset + ( 0 mm ))"
equation "d2054 = abs(2 * panelHeight - mountInset)"
equation "d2058 = frameZ + 14 mm"
equation "d2060 = abs(2 * panelWidth - mountInset + ( 0 mm ) - 4.8 mm)"
equation "d2061 = abs(2 * panelHeight - mountInset - 4.8 mm)"
equation "d2066 = frameZ + 14 mm"
equation "d2068 = abs(2 * panelWidth - mountInset + ( 0 mm ))"
equation "d2069 = abs(2 * panelHeight - mountInset)"
equation "wallGap = 10 mm" comment "Frame rear to wall plane; metal bracket clearance, site-specific"
equation "wallAnchorClearance = 6.5 mm" comment "Placeholder anchor shank clearance; select for actual wall"
equation "d2077 = frameZ + 20 mm"
equation "d2079 = abs(mountInset - 10 mm)"
equation "d2080 = abs(panelHeight / 2 - 15 mm)"
equation "d2085 = frameZ + 23 mm"
equation "d2087 = abs(mountInset + 7 mm)"
equation "d2088 = abs(panelHeight / 2 - 15 mm)"
equation "d2091 = wallGap - 6 mm"
equation "d2093 = frameZ + 20 mm + wallGap - 3 mm"
equation "d2095 = abs(mountInset + 7 mm)"
equation "d2096 = abs(panelHeight / 2 - 15 mm)"
equation "d2101 = frameZ + 20 mm + wallGap - 3 mm"
equation "d2103 = abs(mountInset + 22 mm)"
equation "d2104 = abs(panelHeight / 2)"
equation "d2105 = wallAnchorClearance"
equation "d2108 = frameZ + 20 mm"
equation "d2110 = abs(mountInset)"
equation "d2111 = abs(panelHeight / 2 - 8 mm)"
equation "d2115 = frameZ + 23 mm"
equation "d2117 = abs(mountInset)"
equation "d2118 = abs(panelHeight / 2 - 8 mm)"
equation "d2122 = frameZ + 23 mm"
equation "d2124 = abs(mountInset)"
equation "d2125 = abs(panelHeight / 2 - 8 mm)"
equation "d2129 = frameZ + 14 mm"
equation "d2131 = abs(mountInset - 4.8 mm)"
equation "d2132 = abs(panelHeight / 2 - 8 mm - 4.8 mm)"
equation "d2137 = frameZ + 14 mm"
equation "d2139 = abs(mountInset)"
equation "d2140 = abs(panelHeight / 2 - 8 mm)"
equation "d2146 = frameZ + 20 mm"
equation "d2148 = abs(mountInset)"
equation "d2149 = abs(panelHeight / 2 + 8 mm)"
equation "d2153 = frameZ + 23 mm"
equation "d2155 = abs(mountInset)"
equation "d2156 = abs(panelHeight / 2 + 8 mm)"
equation "d2160 = frameZ + 23 mm"
equation "d2162 = abs(mountInset)"
equation "d2163 = abs(panelHeight / 2 + 8 mm)"
equation "d2167 = frameZ + 14 mm"
equation "d2169 = abs(mountInset - 4.8 mm)"
equation "d2170 = abs(panelHeight / 2 + 8 mm - 4.8 mm)"
equation "d2175 = frameZ + 14 mm"
equation "d2177 = abs(mountInset)"
equation "d2178 = abs(panelHeight / 2 + 8 mm)"
equation "d2184 = frameZ + 20 mm"
equation "d2186 = abs(mountInset - 10 mm)"
equation "d2187 = abs(3 * panelHeight / 2 - 15 mm)"
equation "d2192 = frameZ + 23 mm"
equation "d2194 = abs(mountInset + 7 mm)"
equation "d2195 = abs(3 * panelHeight / 2 - 15 mm)"
equation "d2198 = wallGap - 6 mm"
equation "d2200 = frameZ + 20 mm + wallGap - 3 mm"
equation "d2202 = abs(mountInset + 7 mm)"
equation "d2203 = abs(3 * panelHeight / 2 - 15 mm)"
equation "d2208 = frameZ + 20 mm + wallGap - 3 mm"
equation "d2210 = abs(mountInset + 22 mm)"
equation "d2211 = abs(3 * panelHeight / 2)"
equation "d2212 = wallAnchorClearance"
equation "d2215 = frameZ + 20 mm"
equation "d2217 = abs(mountInset)"
equation "d2218 = abs(3 * panelHeight / 2 - 8 mm)"
equation "d2222 = frameZ + 23 mm"
equation "d2224 = abs(mountInset)"
equation "d2225 = abs(3 * panelHeight / 2 - 8 mm)"
equation "d2229 = frameZ + 23 mm"
equation "d2231 = abs(mountInset)"
equation "d2232 = abs(3 * panelHeight / 2 - 8 mm)"
equation "d2236 = frameZ + 14 mm"
equation "d2238 = abs(mountInset - 4.8 mm)"
equation "d2239 = abs(3 * panelHeight / 2 - 8 mm - 4.8 mm)"
equation "d2244 = frameZ + 14 mm"
equation "d2246 = abs(mountInset)"
equation "d2247 = abs(3 * panelHeight / 2 - 8 mm)"
equation "d2253 = frameZ + 20 mm"
equation "d2255 = abs(mountInset)"
equation "d2256 = abs(3 * panelHeight / 2 + 8 mm)"
equation "d2260 = frameZ + 23 mm"
equation "d2262 = abs(mountInset)"
equation "d2263 = abs(3 * panelHeight / 2 + 8 mm)"
equation "d2267 = frameZ + 23 mm"
equation "d2269 = abs(mountInset)"
equation "d2270 = abs(3 * panelHeight / 2 + 8 mm)"
equation "d2274 = frameZ + 14 mm"
equation "d2276 = abs(mountInset - 4.8 mm)"
equation "d2277 = abs(3 * panelHeight / 2 + 8 mm - 4.8 mm)"
equation "d2282 = frameZ + 14 mm"
equation "d2284 = abs(mountInset)"
equation "d2285 = abs(3 * panelHeight / 2 + 8 mm)"
equation "d2291 = frameZ + 20 mm"
equation "d2293 = abs(2 * panelWidth - mountInset - 10 mm)"
equation "d2294 = abs(panelHeight / 2 - 15 mm)"
equation "d2299 = frameZ + 23 mm"
equation "d2301 = abs(2 * panelWidth - mountInset - 10 mm)"
equation "d2302 = abs(panelHeight / 2 - 15 mm)"
equation "d2305 = wallGap - 6 mm"
equation "d2307 = frameZ + 20 mm + wallGap - 3 mm"
equation "d2309 = abs(2 * panelWidth - mountInset - 32 mm)"
equation "d2310 = abs(panelHeight / 2 - 15 mm)"
equation "d2315 = frameZ + 20 mm + wallGap - 3 mm"
equation "d2317 = abs(2 * panelWidth - mountInset - 22 mm)"
equation "d2318 = abs(panelHeight / 2)"
equation "d2319 = wallAnchorClearance"
equation "d2322 = frameZ + 20 mm"
equation "d2324 = abs(2 * panelWidth - mountInset)"
equation "d2325 = abs(panelHeight / 2 - 8 mm)"
equation "d2329 = frameZ + 23 mm"
equation "d2331 = abs(2 * panelWidth - mountInset)"
equation "d2332 = abs(panelHeight / 2 - 8 mm)"
equation "d2336 = frameZ + 23 mm"
equation "d2338 = abs(2 * panelWidth - mountInset)"
equation "d2339 = abs(panelHeight / 2 - 8 mm)"
equation "d2343 = frameZ + 14 mm"
equation "d2345 = abs(2 * panelWidth - mountInset - 4.8 mm)"
equation "d2346 = abs(panelHeight / 2 - 8 mm - 4.8 mm)"
equation "d2351 = frameZ + 14 mm"
equation "d2353 = abs(2 * panelWidth - mountInset)"
equation "d2354 = abs(panelHeight / 2 - 8 mm)"
equation "d2360 = frameZ + 20 mm"
equation "d2362 = abs(2 * panelWidth - mountInset)"
equation "d2363 = abs(panelHeight / 2 + 8 mm)"
equation "d2367 = frameZ + 23 mm"
equation "d2369 = abs(2 * panelWidth - mountInset)"
equation "d2370 = abs(panelHeight / 2 + 8 mm)"
equation "d2374 = frameZ + 23 mm"
equation "d2376 = abs(2 * panelWidth - mountInset)"
equation "d2377 = abs(panelHeight / 2 + 8 mm)"
equation "d2381 = frameZ + 14 mm"
equation "d2383 = abs(2 * panelWidth - mountInset - 4.8 mm)"
equation "d2384 = abs(panelHeight / 2 + 8 mm - 4.8 mm)"
equation "d2389 = frameZ + 14 mm"
equation "d2391 = abs(2 * panelWidth - mountInset)"
equation "d2392 = abs(panelHeight / 2 + 8 mm)"
equation "d2398 = frameZ + 20 mm"
equation "d2400 = abs(2 * panelWidth - mountInset - 10 mm)"
equation "d2401 = abs(3 * panelHeight / 2 - 15 mm)"
equation "d2406 = frameZ + 23 mm"
equation "d2408 = abs(2 * panelWidth - mountInset - 10 mm)"
equation "d2409 = abs(3 * panelHeight / 2 - 15 mm)"
equation "d2412 = wallGap - 6 mm"
equation "d2414 = frameZ + 20 mm + wallGap - 3 mm"
equation "d2416 = abs(2 * panelWidth - mountInset - 32 mm)"
equation "d2417 = abs(3 * panelHeight / 2 - 15 mm)"
equation "d2422 = frameZ + 20 mm + wallGap - 3 mm"
equation "d2424 = abs(2 * panelWidth - mountInset - 22 mm)"
equation "d2425 = abs(3 * panelHeight / 2)"
equation "d2426 = wallAnchorClearance"
equation "d2429 = frameZ + 20 mm"
equation "d2431 = abs(2 * panelWidth - mountInset)"
equation "d2432 = abs(3 * panelHeight / 2 - 8 mm)"
equation "d2436 = frameZ + 23 mm"
equation "d2438 = abs(2 * panelWidth - mountInset)"
equation "d2439 = abs(3 * panelHeight / 2 - 8 mm)"
equation "d2443 = frameZ + 23 mm"
equation "d2445 = abs(2 * panelWidth - mountInset)"
equation "d2446 = abs(3 * panelHeight / 2 - 8 mm)"
equation "d2450 = frameZ + 14 mm"
equation "d2452 = abs(2 * panelWidth - mountInset - 4.8 mm)"
equation "d2453 = abs(3 * panelHeight / 2 - 8 mm - 4.8 mm)"
equation "d2458 = frameZ + 14 mm"
equation "d2460 = abs(2 * panelWidth - mountInset)"
equation "d2461 = abs(3 * panelHeight / 2 - 8 mm)"
equation "d2467 = frameZ + 20 mm"
equation "d2469 = abs(2 * panelWidth - mountInset)"
equation "d2470 = abs(3 * panelHeight / 2 + 8 mm)"
equation "d2474 = frameZ + 23 mm"
equation "d2476 = abs(2 * panelWidth - mountInset)"
equation "d2477 = abs(3 * panelHeight / 2 + 8 mm)"
equation "d2481 = frameZ + 23 mm"
equation "d2483 = abs(2 * panelWidth - mountInset)"
equation "d2484 = abs(3 * panelHeight / 2 + 8 mm)"
equation "d2488 = frameZ + 14 mm"
equation "d2490 = abs(2 * panelWidth - mountInset - 4.8 mm)"
equation "d2491 = abs(3 * panelHeight / 2 + 8 mm - 4.8 mm)"
equation "d2496 = frameZ + 14 mm"
equation "d2498 = abs(2 * panelWidth - mountInset)"
equation "d2499 = abs(3 * panelHeight / 2 + 8 mm)"
named bodies: "Panel lower left", "Panel lower right", "Panel upper left", "Panel upper right"
